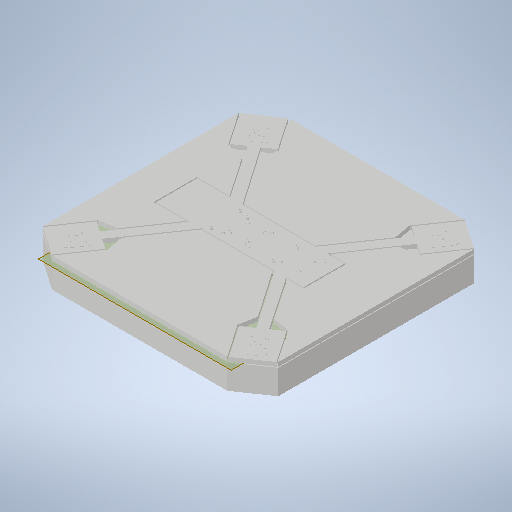
# Autodesk Inventor part: Base Model
Saved by Autodesk Inventor 2025.2 (Build 292293000, 293)
## iProperties
Created: 2026-04-26
Part Number: Base Model
Material: Generic
Document SubType Name: Modeling
Designer: crazi
Density: 1 g/cm^3
Appearance: Default
Author: crazi
Autodesk Inventor part; units mm, degrees
(part 1 of 2)
sketch "Sketch1" plane through (0, 0, 0) normal (0, 1, 0) x (-1, 0, 0)
  line L0 (0, 0) -> (180, 0)
  line L1 (180, 0) -> (180, -50)
  line L2 (180, -50) -> (0, -50)
  line L3 (0, -50) -> (0, 0)
  dimension "d0" = 180
  dimension "d1" = 50
  constraints: 8 end point, 2 parallel, 1 horizontal, 1 perpendicular
  measures "d0" distance of L1.end L2.end
  measures "d1" distance of L0.end L1.end
extrude "Extrusion1" add sketch "Sketch1" along normal blind 5
sketch "Sketch2" plane through (0, 5, 0) normal (0, 1, 0) x (1, 0, 0)
  circle A0 centre (-16, 40) radius 1.75
  circle A1 centre (-21.2113, 35) radius 1.25
  circle A2 centre (-41.2113, 35) radius 1.25
  circle A3 centre (-46.8088, 40.126) radius 1.75
  circle A4 centre (-67.6238, 42.9965) radius 1.75
  circle A5 centre (-78.624, 39.9965) radius 2.25
  circle A6 centre (-83.6239, 34.9965) radius 1.75
  circle A7 centre (-103.6239, 34.9965) radius 1.75
  circle A8 centre (-108.6238, 39.9965) radius 2.25
  circle A9 centre (-119.6241, 42.9965) radius 1.75
  dimension "d16" = 3.5
  dimension "d19" = 2.5
  dimension "d21" = 2.5
  dimension "d24" = 3.5
  dimension "d27" = 3.5
  dimension "d30" = 4.5
  dimension "d33" = 3.5
  dimension "d35" = 3.5
  dimension "d37" = 4.5
  dimension "d40" = 3.5
  constraints: 10 centre point
  measures "d16" diameter of A0
  measures "d19" diameter of A1
  measures "d21" diameter of A2
  measures "d24" diameter of A3
  measures "d27" diameter of A4
  measures "d30" diameter of A5
  measures "d33" diameter of A6
  measures "d35" diameter of A7
  measures "d37" diameter of A8
  measures "d40" diameter of A9
extrude "Extrusion2" cut sketch "Sketch2" against normal blind 5
ref_plane "Work Plane1" through (0, 0, -25) normal (0, 0, 1) x (1, 0, 0)
mirror "Mirror1" about plane through (0, 0, -25) normal (0, 0, 1) of "Extrusion2"
sketch "Sketch5" plane through (0, 5, 0) normal (0, 1, 0) x (1, 0, 0)
  line L0 (-138.8669, 50) -> (-183.4203, 115.2642) projected
  line L1 (-138.8669, 50) -> (-183.4203, 115.2642)
  line L2 (-195.9604, 106.6489) -> (-219.7435, 141.2663) projected
  line L3 (-183.4203, 115.2642) -> (-195.9604, 106.6489)
  line L4 (-195.9604, 106.6489) -> (-219.7435, 141.2663)
  line L5 (-185.2908, 164.9361) -> (-161.5078, 130.3186) projected
  line L6 (-185.2908, 164.9361) -> (-161.5078, 130.3186)
  line L7 (-174.0468, 121.7041) -> (-124.4667, 50) projected
  line L8 (-161.5078, 130.3186) -> (-174.0468, 121.7041)
  line L9 (-174.0468, 121.7041) -> (-124.4667, 50)
  line L10 (-124.4667, 50) -> (-138.8669, 50)
  line L11 (-185.2908, 164.9361) -> (-188.1099, 169.0656)
  line L12 (-185.2908, 164.9361) -> (-180.2908, 164.9361) construction
  line L13 (-219.7435, 141.2663) -> (-222.5748, 145.3874)
  line L14 (-219.7435, 141.2663) -> (-214.7435, 141.2663) construction
  line L15 (-222.5748, 145.3874) -> (-188.1099, 169.0656)
  point P0 (0, 0)
  dimension "d78" = 5
  dimension "d79" = 235.68
  dimension "d81" = 5
  dimension "d82" = 235.51
  constraints: 24 end point, 3 collinear, 3 horizontal, 2 equal length, 1 perpendicular
  measures "d78" distance of L5.start L11.end
  measures "d81" distance of L2.end L13.end
extrude "Extrusion4" add sketch "Sketch5" against normal blind 5
sketch "Sketch3" plane through (0, 5, 0) normal (0, 1, 0) x (1, 0, 0)
  circle A0 centre (-190.57, 135.7115) radius 3.625
  arc A1 (-199.3927, 136.0701) -> (-198.9803, 138.3982) centre (-198.448, 137.1033) ccw
  arc A2 (-198.9803, 138.3982) -> (-199.3927, 136.0701) centre (-199.925, 137.365) ccw
  line L0 (-128.6246, 34.9965) -> (-115.1826, 34.9965) construction
  line L1 (-187.6242, 137.824) -> (-185.6242, 137.824) construction
  line L2 (-190.57, 135.7115) -> (-179.67, 135.7115) construction
  line L3 (-190.57, 135.7115) -> (-169.67, 135.7115) construction
  point P0 (0, 0)
  dimension "d46" = 7.25
  dimension "d49" = 2.8
  dimension "d52" = 2.8
  constraints: 8 end point, 4 horizontal, 4 point on circle, 2 centre point, 1 coincident, 3 other
  measures "d49" diameter of A1
  measures "d52" diameter of A2
extrude "Extrusion5" cut sketch "Sketch3" against normal blind 5
pattern_circular "Circular Pattern1" count 4 over 360 about axis through (-190.57, 5, -135.7115) along (0, -1, 0) of "Extrusion5"
mirror "Mirror2" about plane through (0, 0, -25) normal (0, 0, 1) of "Extrusion5", "Circular Pattern1", "Extrusion4"
ref_plane "Work Plane3" through (-80, 0, -50) normal (-1, 0, 0) x (0, 1, 0)
ref_plane "Work Plane2" through (0, 0, -50) normal (-1, 0, 0) x (0, 1, 0)
mirror "Mirror3" about plane through (-80, 0, -50) normal (-1, 0, 0) of "Extrusion5", "Circular Pattern1", "Extrusion4", "Mirror2"
sketch "Sketch6" plane through (0, 0, 0) normal (0, -1, 0) x (1, 0, 0)
  line L0 (0, 0) -> (-7, 0)
  line L1 (-7, 0) -> (-7, -50)
  line L2 (-7, -50) -> (0, -50)
  line L3 (0, -50) -> (0, 0)
  circle A0 centre (-46.8088, -9.874) radius 1.75 projected
  arc A1 (-55.5237, -15) -> (-60.0237, -15) centre (-57.7737, -15) ccw
  circle A2 centre (-46.8088, -40.126) radius 1.75 projected
  arc A3 (-60.0237, -35) -> (-55.5237, -35) centre (-57.7737, -35) ccw
  line L4 (-60.0237, -35) -> (-60.0237, -15)
  line L5 (-55.5237, -35) -> (-55.5237, -15)
  circle A4 centre (-119.6241, -7.0035) radius 1.75 projected
  arc A5 (-126.7246, -15.0035) -> (-131.2246, -15.0035) centre (-128.9746, -15.0035) ccw
  circle A6 centre (-119.6241, -42.9965) radius 1.75 projected
  arc A7 (-131.2246, -34.9965) -> (-126.7246, -34.9965) centre (-128.9746, -34.9965) ccw
  line L6 (-131.2246, -34.9965) -> (-131.2246, -15.0035)
  line L7 (-126.7246, -15.0035) -> (-126.7246, -34.9965)
  line L8 (-180, -50) -> (-160, -50)
  line L9 (-160, 0) -> (-180, 0)
  line L10 (-180, -37.5) -> (-160, -37.5)
  line L11 (-180, -12.5) -> (-160, -12.5)
  line L12 (-180, -12.5) -> (-180, 0)
  line L13 (-180, -37.5) -> (-180, -50)
  line L14 (-160, -50) -> (-160, -37.5)
  line L15 (-160, -12.5) -> (-160, 0)
  line L16 (-138.8669, -50) -> (-124.4667, -50)
  line L17 (-124.4667, -50) -> (-124.4667, -47)
  line L18 (-124.4667, -47) -> (-138.8669, -47)
  line L19 (-138.8669, -47) -> (-138.8669, -50)
  line L20 (-138.8669, 0) -> (-124.4667, 0)
  line L21 (-124.4667, 0) -> (-124.4667, -3)
  line L22 (-124.4667, -3) -> (-138.8669, -3)
  line L23 (-138.8669, -3) -> (-138.8669, 0)
  line L24 (14.0468, 71.7041) -> (-35.5333, 0) projected
  line L25 (-35.5333, 0) -> (-21.1331, 0)
  line L26 (-21.1331, 0) -> (-21.1331, -3)
  line L27 (-21.1331, -3) -> (-35.5333, -3)
  line L28 (-35.5333, -3) -> (-35.5333, 0)
  line L29 (-35.5333, -50) -> (-21.1331, -50)
  line L30 (-21.1331, -50) -> (-21.1331, -47)
  line L31 (-21.1331, -47) -> (-35.5333, -47)
  line L32 (-35.5333, -47) -> (-35.5333, -50)
  dimension "d83" = 7
  dimension "d84" = 50
  dimension "d87" = 4.5
  dimension "d89" = 4.5
  dimension "d92" = 4.5
  dimension "d95" = 4.5
  dimension "d96" = 20
  dimension "d125" = 3
  dimension "d126" = 3
  constraints: 64 end point, 12 perpendicular, 11 parallel, 8 point on circle, 7 tangent, 6 horizontal, 4 centre point, 1 point on line, 1 vertical
  measures "d83" distance of L2.end L1.end
  measures "d84" distance of L1.end L0.end
  measures "d87" diameter of A1
  measures "d89" diameter of A3
  measures "d92" diameter of A5
  measures "d95" diameter of A7
  measures "d96" distance of L9.end L9.start
  measures "d125" distance of L17.end L16.end
  measures "d126" distance of L20.end L21.end
extrude "Extrusion6" add sketch "Sketch6" along normal blind 25 contours L3 L2 L1 L0 | L5 A3 L4 A1 | L7 A7 L6 A5 | L13 L10 L14 L8 | L15 L11 L12 L9 | L19 L18 L17 L16 | L20 L21 L22 L23 | L25 L26 L27 L28 | L32 L31 L30 L29
fillet "Fillet1" radius 1 8 edges at (-199.3927, 2.5, -136.0701) (-198.9803, 2.5, -138.3982) (-193.2567, 2.5, -127.3012) (-190.9286, 2.5, -126.8888) (-187.8834, 2.5, -144.1218) (-181.7473, 2.5, -135.3529) (-190.2114, 2.5, -144.5342) (-182.1597, 2.5, -133.0249)
ref_plane "Work Plane6" through (0, -25, 0) normal (0, -1, 0) x (1, 0, 0)
sketch "Sketch7" plane through (0, -25, 0) normal (0, -1, 0) x (1, 0, 0)
  line L0 (-180, -50) -> (-160, -50) projected
  line L1 (0, 0) -> (-180, 0)
  line L2 (-180, 0) -> (-180, -50)
  line L3 (-180, -50) -> (0, -50)
  line L4 (0, -50) -> (0, 0)
  line L5 (-41.2113, -35) -> (-21.2113, -35)
  line L6 (-21.2113, -35) -> (-21.2113, -15)
  line L7 (-21.2113, -15) -> (-41.2113, -15)
  line L8 (-41.2113, -35) -> (-48.2113, -35)
  line L9 (-48.2113, -35) -> (-48.2113, -15)
  line L10 (-48.2113, -15) -> (-41.2113, -15)
  line L11 (-126.7246, -34.9965) -> (-116.7246, -34.9965) construction
  circle A0 centre (-118.0644, -29.9965) radius 1.75
  line L12 (-126.7246, -15.0035) -> (-116.7246, -15.0035) construction
  line L13 (-60.0237, -35) -> (-50.0237, -35) construction
  circle A1 centre (-68.684, -30) radius 1.75
  line L14 (-60.0237, -15) -> (-50.0237, -15) construction
  circle A2 centre (-68.684, -20) radius 1.75
  line L15 (-126.7246, -15.0035) -> (-116.7246, -15.0035) construction
  circle A3 centre (-118.0644, -20.0035) radius 1.75
  point P0 (-55.5237, -35)
  dimension "d105" = 20
  dimension "d106" = 7
  dimension "d109" = 3.5
  dimension "d114" = 3.5
  dimension "d117" = 3.5
  dimension "d120" = 3.5
  constraints: 30 end point, 8 horizontal, 4 centre point, 4 parallel, 3 perpendicular
  measures "d105" distance of L6.end L7.end
  measures "d106" distance of L9.end L10.end
  measures "d109" diameter of A0
  measures "d114" diameter of A1
  measures "d117" diameter of A2
  measures "d120" diameter of A3
extrude "Extrusion7" add sketch "Sketch7" along normal blind 6
sketch "Sketch8" plane through (0, -31, 0) normal (0, -1, 0) x (1, 0, 0)
  line L0 (-68.684, -20) -> (-58.684, -20) construction
  line L1 (-126.7246, -34.9965) -> (-60.0237, -35)
  line L2 (-60.0237, -15) -> (-60.0237, -35)
  line L3 (-60.0237, -15) -> (-126.7246, -15.0035)
  line L4 (-126.7246, -15.0035) -> (-126.7246, -34.9965)
  point P0 (0, 0)
  dimension "d121" = 10
  constraints: 10 end point, 1 horizontal
  measures "d121" distance of L0.start L2.start
extrude "Extrusion8" cut sketch "Sketch8" against normal blind 1
sketch "Sketch9" plane through (-55.5237, 0, -15) normal (1, 0, 0) x (0, 0, -1)
  line L0 (14.9965, -18) -> (5.0035, -18)
  line L1 (5.0035, -18) -> (5.0035, -8)
  line L2 (5.0035, -8) -> (14.9965, -8)
  line L3 (14.9965, -8) -> (14.9965, -18)
  point P0 (-15, 0)
  point P1 (0.0035, -25)
  dimension "d130" = 10
  constraints: 8 end point, 2 parallel, 1 horizontal, 1 perpendicular
  measures "d130" distance of L0.end L1.end
extrude "Extrusion9" cut sketch "Sketch9" along normal blind 56.224 and the other way blind 3.8
sketch "Sketch10" plane through (0, 5, 0) normal (0, 1, 0) x (1, 0, 0)
  circle A0 centre (-16, 40) radius 1.75 projected
  circle A1 centre (-21.2113, 35) radius 1.25 projected
  circle A2 centre (-21.2113, 15) radius 1.25 projected
  circle A3 centre (-16, 10) radius 1.75 projected
  circle A4 centre (-41.2113, 35) radius 1.25 projected
  circle A5 centre (-46.8088, 40.126) radius 1.75 projected
  circle A6 centre (-41.2113, 15) radius 1.25 projected
  circle A7 centre (-46.8088, 9.874) radius 1.75 projected
  circle A8 centre (-67.6238, 7.0035) radius 1.75 projected
  circle A9 centre (-78.624, 10.0035) radius 2.25 projected
  circle A10 centre (-83.6239, 15.0035) radius 1.75 projected
  circle A11 centre (-83.6239, 34.9965) radius 1.75 projected
  circle A12 centre (-78.624, 39.9965) radius 2.25 projected
  circle A13 centre (-67.6238, 42.9965) radius 1.75 projected
  circle A14 centre (-103.6239, 34.9965) radius 1.75 projected
  circle A15 centre (-108.6238, 39.9965) radius 2.25 projected
  circle A16 centre (-119.6241, 42.9965) radius 1.75 projected
  circle A17 centre (-103.6239, 15.0035) radius 1.75 projected
  circle A18 centre (-108.6238, 10.0035) radius 2.25 projected
  circle A19 centre (-119.6241, 7.0035) radius 1.75 projected
  circle A20 centre (-190.57, -85.7115) radius 3.625 projected
  arc A21 (-182.4932, -82.9339) -> (-182.0292, -85.5529) centre (-182.692, -84.3197) ccw projected
  arc A22 (-181.4138, -85.4439) -> (-182.0292, -85.5529) centre (-181.5558, -86.4337) ccw projected
  arc A23 (-181.4138, -85.4439) -> (-181.8778, -82.8249) centre (-181.215, -84.0581) ccw projected
  arc A24 (-182.4932, -82.9339) -> (-181.8778, -82.8249) centre (-182.3512, -81.944) ccw projected
  arc A25 (-187.7924, -93.7883) -> (-190.4114, -94.2523) centre (-189.1782, -93.5895) ccw projected
  arc A26 (-187.7924, -93.7883) -> (-187.6834, -94.4037) centre (-186.8025, -93.9303) ccw projected
  arc A27 (-190.3024, -94.8677) -> (-187.6834, -94.4037) centre (-188.9166, -95.0665) ccw projected
  arc A28 (-190.3024, -94.8677) -> (-190.4114, -94.2523) centre (-191.2922, -94.7257) ccw projected
  arc A29 (-193.3476, -77.6347) -> (-193.4567, -77.0193) centre (-194.3375, -77.4927) ccw projected
  arc A30 (-193.3476, -77.6347) -> (-190.7287, -77.1707) centre (-191.9618, -77.8335) ccw projected
  arc A31 (-190.8377, -76.5553) -> (-190.7287, -77.1707) centre (-189.8478, -76.6973) ccw projected
  arc A32 (-190.8377, -76.5553) -> (-193.4567, -77.0193) centre (-192.2235, -76.3565) ccw projected
  arc A33 (-198.6468, -88.4891) -> (-199.1108, -85.8702) centre (-198.448, -87.1033) ccw projected
  arc A34 (-199.7262, -85.9792) -> (-199.1108, -85.8702) centre (-199.5842, -84.9893) ccw projected
  arc A35 (-199.7262, -85.9792) -> (-199.2622, -88.5982) centre (-199.925, -87.365) ccw projected
  circle A36 centre (30.57, -85.7115) radius 3.625 projected
  arc A37 (30.7287, -77.1707) -> (33.3476, -77.6347) centre (31.9618, -77.8335) ccw projected
  arc A38 (33.4567, -77.0193) -> (30.8377, -76.5553) centre (32.2235, -76.3565) ccw projected
  arc A39 (33.4567, -77.0193) -> (33.3476, -77.6347) centre (34.3375, -77.4927) ccw projected
  arc A40 (39.1108, -85.8702) -> (39.7262, -85.9792) centre (39.5842, -84.9893) ccw projected
  arc A41 (39.2622, -88.5982) -> (39.7262, -85.9792) centre (39.925, -87.365) ccw projected
  arc A42 (39.1108, -85.8702) -> (38.6468, -88.4891) centre (38.448, -87.1033) ccw projected
  arc A43 (30.4114, -94.2523) -> (27.7924, -93.7883) centre (29.1782, -93.5895) ccw projected
  arc A44 (30.4114, -94.2523) -> (30.3024, -94.8677) centre (31.2922, -94.7257) ccw projected
  arc A45 (27.6834, -94.4037) -> (30.3024, -94.8677) centre (28.9166, -95.0665) ccw projected
  arc A46 (22.0292, -85.5529) -> (22.4932, -82.9339) centre (22.692, -84.3197) ccw projected
  arc A47 (22.0292, -85.5529) -> (21.4138, -85.4439) centre (21.5558, -86.4337) ccw projected
  arc A48 (21.8778, -82.8249) -> (21.4138, -85.4439) centre (21.215, -84.0581) ccw projected
  arc A49 (-193.4567, 127.0193) -> (-190.8377, 126.5553) centre (-192.2235, 126.3565) ccw projected
  arc A50 (-190.7287, 127.1707) -> (-193.3476, 127.6347) centre (-191.9618, 127.8335) ccw projected
  arc A51 (-193.4567, 127.0193) -> (-193.3476, 127.6347) centre (-194.3375, 127.4927) ccw projected
  arc A52 (-190.7287, 127.1707) -> (-190.8377, 126.5553) centre (-189.8478, 126.6973) ccw projected
  circle A53 centre (-190.57, 135.7115) radius 3.625 projected
  arc A54 (-182.0292, 135.5529) -> (-182.4932, 132.9339) centre (-182.692, 134.3197) ccw projected
  arc A55 (-181.8778, 132.8249) -> (-182.4932, 132.9339) centre (-182.3512, 131.944) ccw projected
  arc A56 (-181.8778, 132.8249) -> (-181.4138, 135.4439) centre (-181.215, 134.0581) ccw projected
  arc A57 (-182.0292, 135.5529) -> (-181.4138, 135.4439) centre (-181.5558, 136.4337) ccw projected
  arc A58 (-190.4114, 144.2523) -> (-187.7924, 143.7883) centre (-189.1782, 143.5895) ccw projected
  arc A59 (-187.6834, 144.4037) -> (-187.7924, 143.7883) centre (-186.8025, 143.9303) ccw projected
  arc A60 (-187.6834, 144.4037) -> (-190.3024, 144.8677) centre (-188.9166, 145.0665) ccw projected
  arc A61 (-190.4114, 144.2523) -> (-190.3024, 144.8677) centre (-191.2922, 144.7257) ccw projected
  circle A62 centre (30.57, 135.7115) radius 3.625 projected
  circle A63 centre (30.57, 135.7115) radius 3.625 projected
  arc A64 (30.7287, -77.1707) -> (30.8377, -76.5553) centre (29.8478, -76.6973) ccw projected
  arc A65 (21.8778, -82.8249) -> (22.4932, -82.9339) centre (22.3512, -81.944) ccw projected
  arc A66 (27.6834, -94.4037) -> (27.7924, -93.7883) centre (26.8025, -93.9303) ccw projected
  arc A67 (39.2622, -88.5982) -> (38.6468, -88.4891) centre (38.7888, -89.479) ccw projected
  circle A68 centre (-190.57, -85.7115) radius 5.025
  arc A69 (-198.6468, -88.4891) -> (-199.2622, -88.5982) centre (-198.7888, -89.479) ccw projected
  arc A70 (-181.4829, -86.8452) -> (-182.4241, -81.5326) centre (-181.215, -84.0581) ccw
  arc A71 (-182.4241, -81.5326) -> (-181.4829, -86.8452) centre (-182.692, -84.3197) ccw
  arc A72 (-186.3911, -93.8574) -> (-191.7037, -94.7986) centre (-189.1782, -93.5895) ccw
  arc A73 (-191.7037, -94.7986) -> (-186.3911, -93.8574) centre (-188.9166, -95.0665) ccw
  arc A74 (-198.7159, -89.8905) -> (-199.6571, -84.5778) centre (-198.448, -87.1033) ccw
  arc A75 (-199.6571, -84.5778) -> (-198.7159, -89.8905) centre (-199.925, -87.365) ccw
  arc A76 (-194.749, -77.5656) -> (-189.4363, -76.6244) centre (-191.9618, -77.8335) ccw
  arc A77 (-189.4363, -76.6244) -> (-194.749, -77.5656) centre (-192.2235, -76.3565) ccw
  circle A78 centre (30.57, -85.7115) radius 5.025
  arc A79 (39.6571, -84.5778) -> (38.7159, -89.8905) centre (38.448, -87.1033) ccw
  arc A80 (38.7159, -89.8905) -> (39.6571, -84.5778) centre (39.925, -87.365) ccw
  arc A81 (31.7037, -94.7986) -> (26.3911, -93.8574) centre (29.1782, -93.5895) ccw
  arc A82 (26.3911, -93.8574) -> (31.7037, -94.7986) centre (28.9166, -95.0665) ccw
  arc A83 (21.4829, -86.8452) -> (22.4241, -81.5326) centre (22.692, -84.3197) ccw
  arc A84 (22.4241, -81.5326) -> (21.4829, -86.8452) centre (21.215, -84.0581) ccw
  arc A85 (29.4363, -76.6244) -> (34.749, -77.5656) centre (31.9618, -77.8335) ccw
  arc A86 (34.749, -77.5656) -> (29.4363, -76.6244) centre (32.2235, -76.3565) ccw
  circle A87 centre (30.57, 135.7115) radius 5.025
  arc A88 (27.7924, 143.7883) -> (30.4114, 144.2523) centre (29.1782, 143.5895) ccw projected
  arc A89 (30.3024, 144.8677) -> (30.4114, 144.2523) centre (31.2922, 144.7257) ccw projected
  arc A90 (30.3024, 144.8677) -> (27.6834, 144.4037) centre (28.9166, 145.0665) ccw projected
  arc A91 (27.7924, 143.7883) -> (27.6834, 144.4037) centre (26.8025, 143.9303) ccw projected
  arc A92 (39.7262, 135.9792) -> (39.2622, 138.5982) centre (39.925, 137.365) ccw projected
  arc A93 (39.7262, 135.9792) -> (39.1108, 135.8702) centre (39.5842, 134.9893) ccw projected
  arc A94 (38.6468, 138.4891) -> (39.1108, 135.8702) centre (38.448, 137.1033) ccw projected
  arc A95 (38.6468, 138.4891) -> (39.2622, 138.5982) centre (38.7888, 139.479) ccw projected
  arc A96 (22.4932, 132.9339) -> (22.0292, 135.5529) centre (22.692, 134.3197) ccw projected
  arc A97 (22.4932, 132.9339) -> (21.8778, 132.8249) centre (22.3512, 131.944) ccw projected
  arc A98 (21.4138, 135.4439) -> (21.8778, 132.8249) centre (21.215, 134.0581) ccw projected
  arc A99 (21.4138, 135.4439) -> (22.0292, 135.5529) centre (21.5558, 136.4337) ccw projected
  arc A100 (39.6571, 134.5778) -> (38.7159, 139.8905) centre (39.925, 137.365) ccw
  arc A101 (38.7159, 139.8905) -> (39.6571, 134.5778) centre (38.448, 137.1033) ccw
  arc A102 (30.8377, 126.5553) -> (33.4567, 127.0193) centre (32.2235, 126.3565) ccw projected
  arc A103 (33.3476, 127.6347) -> (33.4567, 127.0193) centre (34.3375, 127.4927) ccw projected
  arc A104 (33.3476, 127.6347) -> (30.7287, 127.1707) centre (31.9618, 127.8335) ccw projected
  arc A105 (30.8377, 126.5553) -> (30.7287, 127.1707) centre (29.8478, 126.6973) ccw projected
  arc A106 (29.4363, 126.6244) -> (34.749, 127.5656) centre (32.2235, 126.3565) ccw
  arc A107 (34.749, 127.5656) -> (29.4363, 126.6244) centre (31.9618, 127.8335) ccw
  arc A108 (26.3911, 143.8574) -> (31.7037, 144.7986) centre (29.1782, 143.5895) ccw
  arc A109 (31.7037, 144.7986) -> (26.3911, 143.8574) centre (28.9166, 145.0665) ccw
  arc A110 (22.4241, 131.5326) -> (21.4829, 136.8452) centre (22.692, 134.3197) ccw
  arc A111 (21.4829, 136.8452) -> (22.4241, 131.5326) centre (21.215, 134.0581) ccw
  circle A112 centre (-190.57, 135.7115) radius 5.025
  arc A113 (-182.4241, 131.5326) -> (-181.4829, 136.8452) centre (-181.215, 134.0581) ccw
  arc A114 (-181.4829, 136.8452) -> (-182.4241, 131.5326) centre (-182.692, 134.3197) ccw
  arc A115 (-194.749, 127.5656) -> (-189.4363, 126.6244) centre (-192.2235, 126.3565) ccw
  arc A116 (-189.4363, 126.6244) -> (-194.749, 127.5656) centre (-191.9618, 127.8335) ccw
  arc A117 (-191.7037, 144.7986) -> (-186.3911, 143.8574) centre (-189.1782, 143.5895) ccw
  arc A118 (-186.3911, 143.8574) -> (-191.7037, 144.7986) centre (-188.9166, 145.0665) ccw
  arc A119 (-199.1108, 135.8702) -> (-198.6468, 138.4891) centre (-198.448, 137.1033) ccw projected
  arc A120 (-199.1108, 135.8702) -> (-199.7262, 135.9792) centre (-199.5842, 134.9893) ccw projected
  arc A121 (-199.2622, 138.5982) -> (-199.7262, 135.9792) centre (-199.925, 137.365) ccw projected
  arc A122 (-199.2622, 138.5982) -> (-198.6468, 138.4891) centre (-198.7888, 139.479) ccw projected
  arc A123 (-199.6571, 134.5778) -> (-198.7159, 139.8905) centre (-198.448, 137.1033) ccw
  arc A124 (-198.7159, 139.8905) -> (-199.6571, 134.5778) centre (-199.925, 137.365) ccw
  circle A125 centre (-103.6239, 34.9965) radius 3.15
  circle A126 centre (-108.6238, 39.9965) radius 3.65
  circle A127 centre (-119.6241, 42.9965) radius 3.15
  circle A128 centre (-119.6241, 7.0035) radius 3.15
  circle A129 centre (-108.6238, 10.0035) radius 3.65
  circle A130 centre (-103.6239, 15.0035) radius 3.15
  circle A131 centre (-83.6239, 15.0035) radius 3.15
  circle A132 centre (-78.624, 10.0035) radius 3.65
  circle A133 centre (-67.6238, 7.0035) radius 3.15
  circle A134 centre (-46.8088, 9.874) radius 3.15
  circle A135 centre (-41.2113, 15) radius 2.65
  circle A136 centre (-21.2113, 15) radius 2.65
  circle A137 centre (-16, 10) radius 3.15
  circle A138 centre (-16, 40) radius 3.15
  circle A139 centre (-21.2113, 35) radius 2.65
  circle A140 centre (-41.2113, 35) radius 2.65
  circle A141 centre (-46.8088, 40.126) radius 3.15
  circle A142 centre (-67.6238, 42.9965) radius 3.15
  circle A143 centre (-78.624, 39.9965) radius 3.65
  circle A144 centre (-83.6239, 34.9965) radius 3.15
  line L0 (-194.5178, -74.7514) -> (-202.2193, -85.7599)
  line L1 (-190.6184, -74.0622) -> (-179.6099, -81.7638)
  line L2 (-201.5301, -89.6593) -> (-190.5216, -97.3608)
  line L3 (-186.6223, -96.6716) -> (-178.9207, -85.6631)
  line L4 (-197.7953, -72.4585) -> (-205.6343, -83.6634)
  line L5 (-188.3255, -70.7847) -> (-177.317, -78.4862)
  line L6 (-183.3447, -98.9646) -> (-175.6432, -87.9561)
  line L7 (-207.2625, -97.8531) -> (-196.2541, -105.5547)
  arc A145 (-205.6343, -83.6634) -> (-207.2625, -97.8531) centre (-193.3435, -92.262) ccw
  arc A146 (-196.2541, -105.5547) -> (-183.3447, -98.9646) centre (-195.7707, -90.5625) ccw
  arc A147 (-175.6432, -87.9561) -> (-177.317, -78.4862) centre (-181.215, -84.0581) ccw
  arc A148 (-188.3255, -70.7847) -> (-197.7953, -72.4585) centre (-192.2235, -76.3565) ccw
  line L8 (19.6099, -81.7638) -> (30.6184, -74.0622)
  line L9 (34.5178, -74.7514) -> (42.2193, -85.7599)
  line L10 (41.5301, -89.6593) -> (30.5216, -97.3608)
  line L11 (26.6223, -96.6716) -> (18.9207, -85.6631)
  line L12 (17.317, -78.4862) -> (28.3255, -70.7847)
  line L13 (37.7953, -72.4585) -> (45.4968, -83.467)
  line L14 (23.3447, -98.9646) -> (15.6432, -87.9561)
  line L15 (47.2625, -97.8531) -> (36.2541, -105.5547)
  arc A149 (23.3447, -98.9646) -> (36.2541, -105.5547) centre (35.7707, -90.5625) ccw
  arc A150 (47.2625, -97.8531) -> (45.4968, -83.467) centre (33.3443, -92.2599) ccw
  arc A151 (17.317, -78.4862) -> (15.6432, -87.9561) centre (21.215, -84.0581) ccw
  arc A152 (37.7953, -72.4585) -> (28.3255, -70.7847) centre (32.2235, -76.3565) ccw
  line L16 (34.5178, 124.7514) -> (42.2193, 135.7599)
  line L17 (41.5301, 139.6593) -> (30.5216, 147.3608)
  line L18 (26.6223, 146.6716) -> (18.9207, 135.6631)
  line L19 (19.6099, 131.7638) -> (30.5569, 124.1053)
  line L20 (23.3447, 148.9646) -> (15.6432, 137.9561)
  line L21 (17.317, 128.4862) -> (28.264, 120.8277)
  line L22 (37.7953, 122.4585) -> (45.4968, 133.467)
  line L23 (47.2625, 147.8531) -> (36.2541, 155.5547)
  arc A153 (36.2541, 155.5547) -> (23.3447, 148.9646) centre (35.7707, 140.5625) ccw
  arc A154 (45.4968, 133.467) -> (47.2625, 147.8531) centre (33.3443, 142.2599) ccw
  arc A155 (15.6432, 137.9561) -> (17.317, 128.4862) centre (21.215, 134.0581) ccw
  arc A156 (28.264, 120.8277) -> (37.7953, 122.4585) centre (32.2233, 126.3562) ccw
  line L24 (-179.6099, 131.7638) -> (-190.6184, 124.0622)
  line L25 (-178.9207, 135.6631) -> (-186.6223, 146.6716)
  line L26 (-190.5216, 147.3608) -> (-201.5301, 139.6593)
  line L27 (-202.2193, 135.7599) -> (-194.5178, 124.7514)
  line L28 (-196.2541, 155.5547) -> (-207.2625, 147.8531)
  line L29 (-175.6432, 137.9561) -> (-183.3447, 148.9646)
  line L30 (-177.317, 128.4862) -> (-188.3255, 120.7847)
  line L31 (-205.4968, 133.467) -> (-197.7953, 122.4585)
  arc A157 (-207.2625, 147.8531) -> (-205.4968, 133.467) centre (-193.3443, 142.2599) ccw
  arc A158 (-183.3447, 148.9646) -> (-196.2541, 155.5547) centre (-195.7707, 140.5625) ccw
  arc A159 (-177.317, 128.4862) -> (-175.6432, 137.9561) centre (-181.215, 134.0581) ccw
  arc A160 (-197.7953, 122.4585) -> (-188.3255, 120.7847) centre (-192.2235, 126.3565) ccw
  point P0 (0, 0)
  dimension "d135" = 1.4
  dimension "d136" = 1.4
  dimension "d137" = 1.4
  dimension "d138" = 1.4
  dimension "d139" = 1.4
  dimension "d140" = 1.4
  dimension "d141" = 1.4
  dimension "d142" = 1.4
  dimension "d143" = 1.4
  dimension "d144" = 1.4
  dimension "d145" = 1.4
  dimension "d148" = 1.4
  dimension "d149" = 1.4
  dimension "d150" = 1.4
  dimension "d151" = 1.4
  dimension "d152" = 1.4
  dimension "d153" = 1.4
  dimension "d154" = 1.4
  dimension "d155" = 1.4
  dimension "d156" = 1.4
  dimension "d157" = 1.4
  dimension "d158" = 1.4
  dimension "d159" = 1.4
  dimension "d160" = 1.4
  dimension "d161" = 1.4
  dimension "d162" = 1.4
  dimension "d163" = 1.4
  dimension "d164" = 1.4
  dimension "d165" = 1.4
  dimension "d166" = 1.4
  dimension "d167" = 1.4
  dimension "d168" = 1.4
  dimension "d169" = 1.4
  dimension "d170" = 1.4
  dimension "d171" = 1.4
  dimension "d172" = 1.4
  dimension "d173" = 1.4
  dimension "d174" = 1.4
  dimension "d175" = 1.4
  dimension "d176" = 1.4
  dimension "d241" = 4
  dimension "d242" = 4
  dimension "d243" = 4
  dimension "d244" = 10
  dimension "d245" = 15
  dimension "d246" = 15
  dimension "d247" = 6.8
  dimension "d248" = 6.8
  dimension "d249" = 4
  dimension "d250" = 4
  dimension "d251" = 4
  dimension "d252" = 10
  dimension "d253" = 15
  dimension "d254" = 15
  dimension "d255" = 6.8
  dimension "d256" = 6.8
  dimension "d257" = 4
  dimension "d258" = 4
  dimension "d259" = 4
  dimension "d260" = 10
  dimension "d261" = 15
  dimension "d262" = 15
  dimension "d263" = 6.8
  dimension "d264" = 6.8
  constraints: 127 point on circle, 72 centre point, 64 end point, 30 tangent, 16 parallel, 3 perpendicular, 16 other
  measures "d135" radial gap between concentric circles of A20 A68
  measures "d136" radial gap between concentric circles of A23 A70
  measures "d137" radial gap between concentric circles of A25 A72
  measures "d138" radial gap between concentric circles of A33 A74
  measures "d139" radial gap between concentric circles of A30 A76
  measures "d140" radial gap between concentric circles of A36 A78
  measures "d141" radial gap between concentric circles of A42 A79
  measures "d142" radial gap between concentric circles of A43 A81
  measures "d143" radial gap between concentric circles of A48 A84
  measures "d144" radial gap between concentric circles of A37 A85
  measures "d145" radial gap between concentric circles of A62 A87
  measures "d148" radial gap between concentric circles of A94 A101
  measures "d149" radial gap between concentric circles of A102 A106
  measures "d150" radial gap between concentric circles of A88 A108
  measures "d151" radial gap between concentric circles of A98 A111
  measures "d152" radial gap between concentric circles of A53 A112
  measures "d153" radial gap between concentric circles of A56 A113
  measures "d154" radial gap between concentric circles of A49 A115
  measures "d155" radial gap between concentric circles of A58 A117
  measures "d156" radial gap between concentric circles of A119 A123
  measures "d157" radial gap between concentric circles of A14 A125
  measures "d158" radial gap between concentric circles of A15 A126
  measures "d159" radial gap between concentric circles of A16 A127
  measures "d160" radial gap between concentric circles of A19 A128
  measures "d161" radial gap between concentric circles of A18 A129
  measures "d162" radial gap between concentric circles of A17 A130
  measures "d163" radial gap between concentric circles of A10 A131
  measures "d164" radial gap between concentric circles of A9 A132
  measures "d165" radial gap between concentric circles of A8 A133
  measures "d166" radial gap between concentric circles of A7 A134
  measures "d167" radial gap between concentric circles of A6 A135
  measures "d168" radial gap between concentric circles of A2 A136
  measures "d169" radial gap between concentric circles of A3 A137
  measures "d170" radial gap between concentric circles of A0 A138
  measures "d171" radial gap between concentric circles of A1 A139
  measures "d172" radial gap between concentric circles of A4 A140
  measures "d173" radial gap between concentric circles of A5 A141
  measures "d174" radial gap between concentric circles of A13 A142
  measures "d175" radial gap between concentric circles of A12 A143
  measures "d176" radial gap between concentric circles of A11 A144
  measures "d241" distance between parallel lines of L0 L4
  measures "d242" distance between parallel lines of L1 L5
  measures "d243" distance between parallel lines of L3 L6
  measures "d244" distance between parallel lines of L2 L7
  measures "d245" radius of A146
  measures "d246" radius of A145
  measures "d247" radius of A147
  measures "d248" radius of A148
  measures "d249" distance between parallel lines of L8 L12
  measures "d250" distance between parallel lines of L9 L13
  measures "d251" distance between parallel lines of L11 L14
  measures "d252" distance between parallel lines of L10 L15
  measures "d253" radius of A149
  measures "d254" radius of A150
  measures "d255" radius of A151
  measures "d256" radius of A152
  measures "d257" distance between parallel lines of L18 L20
  measures "d258" distance between parallel lines of L19 L21
  measures "d259" distance between parallel lines of L16 L22
  measures "d260" distance between parallel lines of L17 L23
  measures "d261" radius of A153
  measures "d262" radius of A154
  measures "d263" radius of A155
  measures "d264" radius of A156
extrude "Extrusion10" add sketch "Sketch10" against normal blind 5 separate body contours A20 | A24 A23 A22 A21 | A26 A27 A28 A25 | A29 A32 A31 A30 | A69 A35 A34 A33 | A68 | A71 A70 | A70 L3 A73 A72 L2 A75 A74 L0 A77 A76 L1 A71 | A73 A72 | A77 A76 | A75 A74 | A148 L5 A147 L6 A146 L7 A145 L4
extrude "Extrusion11" add sketch "Sketch10" against normal blind 5 separate body contours A36 | A64 A38 A39 A37 | A40 A41 A67 A42 | A44 A45 A66 A43 | A47 A48 A65 A46 | A78 | A80 A79 | A79 A80 L10 A82 A81 L11 A84 A83 L8 A86 A85 L9 | A86 A85 | A82 A81 | A84 A83 | L12 A152 L13 A150 L15 A149 L14 A151
extrude "Extrusion12" add sketch "Sketch10" against normal blind 5 separate body contours A62 | A87 | A91 A90 A89 A88 | A93 A94 A95 A92 | A97 A98 A99 A96 | A101 A100 | A100 L16 A106 A107 L19 A111 A110 L18 A109 A108 L17 A101 | A106 A107 | A109 A108 | A111 A110 | A105 A104 A103 A102 | A153 L23 A154 L22 A156 L21 A155 L20
extrude "Extrusion13" add sketch "Sketch10" against normal blind 5 separate body contours A51 A50 A52 A49 | A53 | A57 A56 A55 A54 | A61 A60 A59 A58 | A112 | A114 A113 | A113 L24 A115 A116 L27 A124 A123 L26 A118 A117 L25 A114 | A115 A116 | A118 A117 | A124 A123 | A120 A121 A122 A119 | A158 L29 A159 L30 A160 L31 A157 L28
extrude "Extrusion14" add sketch "Sketch10" against normal blind 5 separate body contours A125 | A126 | A127 | A128 | A129 | A130 | A131 | A132 | A133 | A134 | A135 | A136 | A137 | A138 | A139 | A140 | A141 | A142 | A143 | A144
sketch "Sketch11" plane through (0, -31, 0) normal (0, -1, 0) x (1, 0, 0)
  line L0 (-48.2113, -15) -> (-21.2113, -15) projected
  line L1 (-48.2113, -35) -> (-48.2113, -15) projected
  line L2 (-21.2113, -15) -> (-21.2113, -35) projected
  line L3 (-21.2113, -35) -> (-48.2113, -35) projected
  line L4 (-60.0237, -15) -> (-60.0237, -35) projected
  line L5 (-126.7246, -15.0035) -> (-60.0237, -15) projected
  line L6 (-60.0237, -35) -> (-126.7246, -34.9965) projected
  line L7 (-126.7246, -34.9965) -> (-126.7246, -15.0035) projected
  line L8 (-19.8113, -13.6) -> (-49.6113, -13.6)
  line L9 (-49.6113, -13.6) -> (-49.6113, -36.4)
  line L10 (-49.6113, -36.4) -> (-19.8113, -36.4)
  line L11 (-19.8113, -36.4) -> (-19.8113, -13.6)
  line L12 (-128.1246, -36.3965) -> (-58.6237, -36.4001)
  line L13 (-58.6237, -36.4001) -> (-58.6237, -13.5999)
  line L14 (-58.6237, -13.5999) -> (-128.1246, -13.6035)
  line L15 (-128.1246, -13.6035) -> (-128.1246, -36.3965)
  point P0 (0, 0)
  dimension "d187" = 1.4
  dimension "d188" = 1.4
  constraints: 16 end point, 6 other
  measures "d187" distance between parallel lines of L0 L8
  measures "d188" distance between parallel lines of L6 L12
extrude "Extrusion15" add sketch "Sketch11" against normal blind 6 separate body
sketch "Sketch12" plane through (0, 5, 0) normal (1, 0, 0) x (0, 0, -1)
  line L0 (29.9965, -23) -> (20.0035, -23) projected
  line L1 (20.0035, -23) -> (20.0035, -13) projected
  line L2 (20.0035, -13) -> (29.9965, -13) projected
  line L3 (29.9965, -13) -> (29.9965, -23) projected
  line L4 (31.3965, -11.6) -> (18.6035, -11.6)
  line L5 (18.6035, -11.6) -> (18.6035, -24.4)
  line L6 (18.6035, -24.4) -> (31.3965, -24.4)
  line L7 (31.3965, -24.4) -> (31.3965, -11.6)
  point P0 (0, -5)
  dimension "d191" = 1.4
  constraints: 8 end point, 3 other
  measures "d191" distance between parallel lines of L2 L4
extrude "Extrusion16" add sketch "Sketch12" against normal up to surface (7 mm away) separate body
sketch "Sketch14" plane through (-60.0237, 0, -35) normal (-1, 0, 0) x (0, 0, 1)
  line L0 (5.0035, -8) -> (14.9965, -8) projected
  line L1 (14.9965, -8) -> (14.9965, -18) projected
  line L2 (14.9965, -18) -> (5.0035, -18) projected
  line L3 (5.0035, -18) -> (5.0035, -8) projected
  line L4 (3.6035, -19.4) -> (16.3965, -19.4)
  line L5 (16.3965, -19.4) -> (16.3965, -6.6)
  line L6 (16.3965, -6.6) -> (3.6035, -6.6)
  line L7 (3.6035, -6.6) -> (3.6035, -19.4)
  point P0 (35, 0)
  dimension "d194" = 1.4
  constraints: 8 end point, 3 other
  measures "d194" distance between parallel lines of L2 L4
extrude "Extrusion17" add sketch "Sketch14" against normal blind 3.8 separate body
ref_plane "Work Plane7" through (0, -1, 0) normal (0, -1, 0) x (1, 0, 0)
sketch "Sketch16" plane through (0, -1, 0) normal (0, -1, 0) x (1, 0, 0)
  line L0 (-124.4667, -47) -> (-62.4667, -47)
  line L1 (-62.4667, -47) -> (-62.4667, -3)
  line L2 (-62.4667, -3) -> (-124.4667, -3)
  line L3 (-124.4667, -3) -> (-124.4667, -47)
  line L4 (-62.4667, -3) -> (-53.2667, -3) construction
  line L5 (-53.2667, -3) -> (-8.8154, -3)
  line L6 (-8.8154, -47) -> (-53.2667, -47)
  line L7 (-53.2667, -47) -> (-53.2667, -3)
  line L8 (-8.8154, -47) -> (-8.8154, -3)
  point P0 (0, 0)
  dimension "d205" = 62
  dimension "d206" = 44
  constraints: 18 end point, 3 horizontal, 3 parallel, 2 perpendicular
  measures "d205" distance of L2.end L1.end
  measures "d206" distance of L1.end L0.end
extrude "Extrusion19" add sketch "Sketch16" along normal blind 23 separate body
sketch "Sketch17" plane through (0, 0, 0) normal (0, 1, 0) x (-1, 0, 0)
  line L0 (174.0468, 71.7041) -> (124.4667, 0) projected
  line L1 (161.5078, 80.3186) -> (174.0468, 71.7041) projected
  line L2 (185.2908, 114.9361) -> (161.5078, 80.3186) projected
  line L3 (188.1099, 119.0656) -> (185.2908, 114.9361) projected
  line L4 (-14.0468, 71.7041) -> (35.5333, 0) projected
  line L5 (-1.5078, 80.3186) -> (-14.0468, 71.7041) projected
  line L6 (-25.2908, 114.9361) -> (-1.5078, 80.3186) projected
  line L7 (-28.1099, 119.0656) -> (-25.2908, 114.9361) projected
  line L8 (124.4667, 0) -> (35.5333, 0) projected
  line L9 (-26.8711, 119.9113) -> (-24.0532, 115.7836)
  line L10 (-24.0532, 115.7836) -> (0.5779, 79.9317)
  line L11 (-3.3336, 58.8478) -> (36.3198, 1.5)
  line L12 (36.3198, 1.5) -> (123.6802, 1.5)
  line L13 (123.6802, 1.5) -> (163.3336, 58.8478)
  line L14 (159.4221, 79.9317) -> (184.0532, 115.7836)
  line L15 (184.0532, 115.7836) -> (186.8711, 119.9113)
  line L16 (159.4221, 79.9317) -> (163.3336, 58.8478)
  line L17 (159.4221, 79.9317) -> (180.8658, 79.9317) construction
  line L18 (0.5779, 79.9317) -> (-3.3336, 58.8478)
  line L19 (0.5779, 79.9317) -> (22.0216, 79.9317) construction
  line L20 (186.8711, 119.9113) -> (-26.8711, 119.9113)
  line L21 (-26.8711, -169.9113) -> (-24.0532, -165.7836)
  line L22 (-24.0532, -165.7836) -> (0.5779, -129.9317)
  line L23 (-3.3336, -108.8478) -> (36.3198, -51.5)
  line L24 (36.3198, -51.5) -> (123.6802, -51.5)
  line L25 (123.6802, -51.5) -> (163.3336, -108.8478)
  line L26 (159.4221, -129.9317) -> (184.0532, -165.7836)
  line L27 (184.0532, -165.7836) -> (186.8711, -169.9113)
  line L28 (159.4221, -129.9317) -> (163.3336, -108.8478)
  line L29 (0.5779, -129.9317) -> (-3.3336, -108.8478)
  line L30 (186.8711, -169.9113) -> (-26.8711, -169.9113)
  line L31 (195.9604, -106.6489) -> (222.5748, -145.3874) projected
  line L32 (183.4203, -115.2642) -> (195.9604, -106.6489) projected
  line L33 (138.8669, -50) -> (183.4203, -115.2642) projected
  line L34 (180, -50) -> (0, -50) projected
  line L35 (180, 0) -> (180, -50) projected
  line L36 (0, 0) -> (180, 0) projected
  line L37 (138.8669, 0) -> (183.4203, 65.2642) projected
  line L38 (183.4203, 65.2642) -> (195.9604, 56.6489) projected
  line L39 (195.9604, 56.6489) -> (222.5748, 95.3874) projected
  line L40 (223.8111, -144.538) -> (196.3474, -104.5631)
  line L41 (36.3198, -51.5) -> (123.6802, -51.5)
  line L42 (141.7071, -51.5) -> (181.4, -51.5)
  line L43 (175.2607, -100.6512) -> (141.7071, -51.5)
  line L44 (140.6831, -50) -> (140.1058, -49.1543)
  line L45 (181.4, 1.5) -> (141.7071, 1.5)
  line L46 (123.6802, 1.5) -> (36.3198, 1.5)
  line L47 (223.8111, 94.538) -> (196.3474, 54.5631)
  line L48 (175.21, 50.5768) -> (141.7071, 1.5)
  line L49 (140.6831, 0) -> (140.1058, -0.8457)
  line L50 (223.8111, -144.538) -> (223.8111, 94.538)
  line L51 (196.3474, -104.5631) -> (175.2607, -100.6512)
  line L52 (196.3474, -104.5631) -> (217.7938, -104.5631) construction
  line L53 (196.3474, 54.5631) -> (175.21, 50.5768)
  line L54 (196.3474, 54.5631) -> (217.8573, 54.5631) construction
  line L55 (-35.9604, -106.6489) -> (-62.5748, -145.3874) projected
  line L56 (-23.4203, -115.2642) -> (-35.9604, -106.6489) projected
  line L57 (21.1331, -50) -> (-23.4203, -115.2642) projected
  line L58 (0, -50) -> (0, 0) projected
  line L59 (21.1331, 0) -> (-23.4203, 65.2642) projected
  line L60 (-23.4203, 65.2642) -> (-35.9604, 56.6489) projected
  line L61 (-35.9604, 56.6489) -> (-62.5748, 95.3874) projected
  line L62 (-36.3216, -104.7022) -> (-63.7287, -144.5947)
  line L63 (-63.7287, 94.5947) -> (-36.3216, 54.7022)
  line L64 (181.4, 1.4) -> (181.4, -51.4)
  line L65 (-1.4, -51.4) -> (-1.4, 1.4)
  line L66 (-1.4, -51.4) -> (18.4822, -51.4)
  line L67 (-1.4, 1.4) -> (18.4822, 1.4)
  line L68 (-15.4983, 51.1764) -> (18.4822, 1.4)
  line L69 (19.4379, 0) -> (19.9768, -0.7893)
  line L70 (19.9768, -49.2107) -> (19.4379, -50)
  line L71 (18.4822, -51.4) -> (-15.3674, -100.9848)
  line L72 (-63.7287, -144.5947) -> (-63.7287, 94.5947)
  line L73 (181.4, 1.4) -> (181.4, 1.5)
  line L74 (181.4, -51.4) -> (181.4, -51.5)
  line L75 (-36.3216, -104.7022) -> (-15.3674, -100.9848)
  line L76 (-36.3216, -104.7022) -> (-15.0402, -104.7022) construction
  line L77 (-36.3216, 54.7022) -> (-15.4983, 51.1764)
  line L78 (-36.3216, 54.7022) -> (-15.2019, 54.7022) construction
  dimension "d213" = 1.5
  dimension "d214" = 79.49
  dimension "d215" = 100.51
  dimension "d216" = 1.5
  dimension "d218" = 1.5
  dimension "d219" = 190.51
  dimension "d220" = 190.68
  dimension "d222" = 1.4
  dimension "d223" = 1.4
  dimension "d224" = 10.06
  dimension "d225" = 9.61
  constraints: 108 end point, 8 horizontal, 6 equal length, 4 point on line, 2 perpendicular, 2 vertical, 1 parallel, 2 other
  measures "d213" distance between parallel lines of L0 L13
  measures "d214" angle of L16 L17
  measures "d215" angle of L18 L19
  measures "d216" distance between parallel lines of L31 L40
  measures "d218" distance between parallel lines of L39 L47
  measures "d222" distance between parallel lines of L61 L63
  measures "d223" distance between parallel lines of L58 L65
  measures "d224" angle of L76 L75
  measures "d225" angle of L77 L78
extrude "Extrusion20" add sketch "Sketch17" along normal blind 5 separate body contours L20 L15 L14 L16 L13 L12 L11 L18 L10 L9 | L21 L22 L29 L23 L24 L25 L28 L26 L27 L30 | L40 L51 L43 L42 L74 L64 L73 L45 L48 L53 L47 L50 | L62 L72 L63 L77 L68 L67 L65 L66 L71 L75
ref_plane "Work Plane8" through (0, -1, 0) normal (0, -1, 0) x (1, 0, 0)
sketch "Sketch18" plane through (0, -1, 0) normal (0, -1, 0) x (1, 0, 0)
  line L0 (-223.8111, -144.538) -> (-223.8111, 94.538) projected
  line L1 (-222.5748, 95.3874) -> (-188.1099, 119.0656) projected
  line L2 (-186.8711, 119.9113) -> (26.8711, 119.9113) projected
  line L3 (62.5748, 95.3874) -> (28.1099, 119.0656) projected
  line L4 (63.7287, 94.5947) -> (63.7287, -144.5947) projected
  line L5 (62.5748, -145.3874) -> (28.1099, -169.0656) projected
  line L6 (26.8711, -169.9113) -> (-186.8711, -169.9113) projected
  line L7 (-222.5748, -145.3874) -> (-188.1099, -169.0656) projected
  line L8 (63.7287, 94.5947) -> (62.5748, 95.3874)
  line L9 (26.8711, 119.9113) -> (28.1099, 119.0656)
  line L10 (-186.8711, 119.9113) -> (-188.1099, 119.0656)
  line L11 (-223.8111, 94.538) -> (-222.5748, 95.3874)
  line L12 (-196.3474, -104.5631) -> (-223.8111, -144.538) projected
  line L13 (-222.5748, -145.3874) -> (-195.9604, -106.6489) projected
  line L14 (-223.8111, -144.538) -> (-222.5748, -145.3874)
  line L15 (-186.8711, -169.9113) -> (-184.0532, -165.7836) projected
  line L16 (-186.8711, -169.9113) -> (-188.1099, -169.0656)
  line L17 (1.5078, -130.3186) -> (25.2908, -164.9361) projected
  line L18 (26.8711, -169.9113) -> (28.1099, -169.0656)
  line L19 (62.5748, -145.3874) -> (63.7287, -144.5947)
  line L20 (1.4, -51.4) -> (-181.4, -51.4)
  line L21 (-181.4, -51.4) -> (-181.4, 1.4)
  line L22 (-181.4, 1.4) -> (1.4, 1.4)
  line L23 (1.4, 1.4) -> (1.4, -51.4)
  constraints: 24 end point, 1 collinear, 1 perpendicular
extrude "Extrusion21" add sketch "Sketch18" along normal up to surface (30 mm away) separate body
sketch "Sketch19" plane through (0, -30, 0) normal (0, -1, 0) x (1, 0, 0)
  line L0 (-60.0237, -35) -> (-126.7246, -34.9965) projected
  line L1 (-126.7246, -34.9965) -> (-126.7246, -15.0035) projected
  line L2 (-126.7246, -15.0035) -> (-60.0237, -15) projected
  line L3 (-60.0237, -15) -> (-60.0237, -35) projected
  circle A0 centre (-68.684, -30) radius 1.75 projected
  circle A1 centre (-68.684, -20) radius 1.75 projected
  circle A2 centre (-118.0644, -29.9965) radius 1.75 projected
  circle A3 centre (-118.0644, -20.0035) radius 1.75 projected
  point P0 (0, 0)
extrude "Extrusion22" add sketch "Sketch19" against normal blind 5 separate body
sketch "Sketch20" plane through (0, -31, 0) normal (0, -1, 0) x (1, 0, 0)
  line L0 (-180, -50) -> (-180, 0) projected
  line L1 (-126.7246, -34.9965) -> (-126.7246, -15.0035) projected
  line L2 (-165, -25) -> (-165, -18)
  line L3 (-165, -18) -> (-151, -18)
  line L4 (-151, -18) -> (-151, -32)
  line L5 (-151, -32) -> (-165, -32)
  line L6 (-165, -32) -> (-165, -25)
  point P0 (0, 0)
  dimension "d235" = 7
  dimension "d236" = 14
  dimension "d237" = 14
  dimension "d238" = 14
  constraints: 10 end point, 2 perpendicular, 1 point on line
  measures "d235" distance of L2.start L2.end
  measures "d236" distance of L2.end L3.end
  measures "d237" distance of L3.end L4.end
  measures "d238" distance of L4.end L5.end
extrude "Extrusion23" add sketch "Sketch20" against normal blind 5 separate body